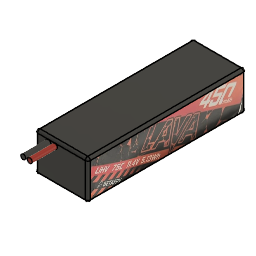
Sesame-DRONE-v127 (Autodesk Fusion 360 archive; units mm, degrees)
design "Lava 450mAh 3S"
Autodesk Fusion 360 part; units mm, degrees
sketch "Sketch1" plane through (0, 0, 0) normal (0, 0, 1) x (1, 0, 0)
  line L0 (0, 0) -> (21, 0)
  line L1 (21, 0) -> (21, 63)
  line L2 (21, 63) -> (0, 63)
  line L3 (0, 63) -> (0, 0)
  dimension "d1" = 21
  dimension "d2" = 63
  constraint horizontal L0
  constraint vertical L1
  constraint horizontal L2
  constraint vertical L3
  constraint coincident L0.start L3.end
  measures "d1" distance of L0.start L0.end
  measures "d2" distance of L0.start L2.end
extrude "Extrude1" add sketch "Sketch1" along normal blind 15.5
fillet "Fillet1" radius 1 12 edges at (21, 31.5, 15.5) (0, 31.5, 15.5) (0, 31.5, 0) (21, 31.5, 0) (21, 0, 7.75) (0, 0, 7.75) (10.5, 0, 15.5) (10.5, 0, 0) (21, 63, 7.75) (10.5, 63, 0) (0, 63, 7.75) (10.5, 63, 15.5)
sketch "Sketch2" plane through (0, 0, 0) normal (0, -1, 0) x (1, 0, 0)
  line L0 (1, 14.5) -> (1, 1)
  line L1 (1, 1) -> (20, 1)
  line L2 (20, 1) -> (20, 14.5)
  line L3 (20, 14.5) -> (1, 14.5)
  circle A0 centre (5.3125, 13.4486) radius 1
  circle A1 centre (7.9093, 13.4486) radius 1
  dimension "d7" = 2
  dimension "d8" = 2
  constraint horizontal A0.centre A1.centre
  measures "d7" diameter of A0
  measures "d8" diameter of A1
extrude "Extrude2" add sketch "Sketch2" along normal blind 10 contours A0 | A1
